Autodesk Fusion 360 part; units mm, degrees
(part 4 of 7)
extrude "Knee mount fastening and lightening (1)" cut sketch "Knee mount fastening and lightening" along normal blind 3 bodies 14 in component "05 | Femur horn link"
ref_plane "WorkPlane4" through (0, 4, 0) normal (0, 1, 0) x (0, 0, 1) in component "05 | Femur horn link"
sketch "Tibia swing clearance" plane through (0, 4, 0) normal (0, 1, 0) x (1, 0, 0) in component "05 | Femur horn link"
  line L0 (26.5, 20) -> (40, 20)
  line L1 (40, 20) -> (40, -20)
  line L2 (40, -20) -> (26.5, -20)
  line L3 (26.5, -20) -> (26.5, 20)
extrude "Tibia swing clearance (1)" cut sketch "Tibia swing clearance" along normal blind 3 bodies 14 in component "05 | Femur horn link"
ref_plane "WorkPlane1" through (0, 25, 0) normal (0, 1, 0) x (0, 0, 1) in component "06 | Knee servo mount"
sketch "Knee frame" plane through (0, 25, 0) normal (0, 1, 0) x (1, 0, 0) in component "06 | Knee servo mount"
  line L0 (19, 13.5) -> (56, 13.5)
  line L1 (56, 13.5) -> (56, -13.5)
  line L2 (56, -13.5) -> (19, -13.5)
  line L3 (19, -13.5) -> (19, 13.5)
extrude "Knee frame (1)" add sketch "Knee frame" along normal blind 3 separate body makes body 15 in component "06 | Knee servo mount"
ref_plane "WorkPlane2" through (0, 25, 0) normal (0, 1, 0) x (0, 0, 1) in component "06 | Knee servo mount"
sketch "MG90S knee body clearance" plane through (0, 25, 0) normal (0, 1, 0) x (1, 0, 0) in component "06 | Knee servo mount"
  line L0 (25.7, 6.5) -> (49.1, 6.5)
  line L1 (49.1, 6.5) -> (49.1, -6.5)
  line L2 (49.1, -6.5) -> (25.7, -6.5)
  line L3 (25.7, -6.5) -> (25.7, 6.5)
extrude "MG90S knee body clearance (1)" cut sketch "MG90S knee body clearance" along normal blind 3 bodies 15 in component "06 | Knee servo mount"
ref_plane "WorkPlane3" through (0, 25, 0) normal (0, 1, 0) x (0, 0, 1) in component "06 | Knee servo mount"
sketch "Knee ear mounting adjustment" plane through (0, 25, 0) normal (0, 1, 0) x (1, 0, 0) in component "06 | Knee servo mount"
  line L0 (24.6, 1.2) -> (24.9106, 1.1591)
  line L1 (24.9106, 1.1591) -> (25.2, 1.0392)
  line L2 (25.2, 1.0392) -> (25.4485, 0.8485)
  line L3 (25.4485, 0.8485) -> (25.6392, 0.6)
  line L4 (25.6392, 0.6) -> (25.7591, 0.3106)
  line L5 (25.7591, 0.3106) -> (25.8, 0)
  line L6 (25.8, 0) -> (25.7591, -0.3106)
  line L7 (25.7591, -0.3106) -> (25.6392, -0.6)
  line L8 (25.6392, -0.6) -> (25.4485, -0.8485)
  line L9 (25.4485, -0.8485) -> (25.2, -1.0392)
  line L10 (25.2, -1.0392) -> (24.9106, -1.1591)
  line L11 (24.9106, -1.1591) -> (24.6, -1.2)
  line L12 (24.6, -1.2) -> (22.4, -1.2)
  line L13 (22.4, -1.2) -> (22.0894, -1.1591)
  line L14 (22.0894, -1.1591) -> (21.8, -1.0392)
  line L15 (21.8, -1.0392) -> (21.5515, -0.8485)
  line L16 (21.5515, -0.8485) -> (21.3608, -0.6)
  line L17 (21.3608, -0.6) -> (21.2409, -0.3106)
  line L18 (21.2409, -0.3106) -> (21.2, 0)
  line L19 (21.2, 0) -> (21.2409, 0.3106)
  line L20 (21.2409, 0.3106) -> (21.3608, 0.6)
  line L21 (21.3608, 0.6) -> (21.5515, 0.8485)
  line L22 (21.5515, 0.8485) -> (21.8, 1.0392)
  line L23 (21.8, 1.0392) -> (22.0894, 1.1591)
  line L24 (22.0894, 1.1591) -> (22.4, 1.2)
  line L25 (22.4, 1.2) -> (24.6, 1.2)
  line L26 (52.4, 1.2) -> (52.7106, 1.1591)
  line L27 (52.7106, 1.1591) -> (53, 1.0392)
  line L28 (53, 1.0392) -> (53.2485, 0.8485)
  line L29 (53.2485, 0.8485) -> (53.4392, 0.6)
  line L30 (53.4392, 0.6) -> (53.5591, 0.3106)
  line L31 (53.5591, 0.3106) -> (53.6, 0)
  line L32 (53.6, 0) -> (53.5591, -0.3106)
  line L33 (53.5591, -0.3106) -> (53.4392, -0.6)
  line L34 (53.4392, -0.6) -> (53.2485, -0.8485)
  line L35 (53.2485, -0.8485) -> (53, -1.0392)
  line L36 (53, -1.0392) -> (52.7106, -1.1591)
  line L37 (52.7106, -1.1591) -> (52.4, -1.2)
  line L38 (52.4, -1.2) -> (50.2, -1.2)
  line L39 (50.2, -1.2) -> (49.8894, -1.1591)
  line L40 (49.8894, -1.1591) -> (49.6, -1.0392)
  line L41 (49.6, -1.0392) -> (49.3515, -0.8485)
  line L42 (49.3515, -0.8485) -> (49.1608, -0.6)
  line L43 (49.1608, -0.6) -> (49.0409, -0.3106)
  line L44 (49.0409, -0.3106) -> (49, 0)
  line L45 (49, 0) -> (49.0409, 0.3106)
  line L46 (49.0409, 0.3106) -> (49.1608, 0.6)
  line L47 (49.1608, 0.6) -> (49.3515, 0.8485)
  line L48 (49.3515, 0.8485) -> (49.6, 1.0392)
  line L49 (49.6, 1.0392) -> (49.8894, 1.1591)
  line L50 (49.8894, 1.1591) -> (50.2, 1.2)
  line L51 (50.2, 1.2) -> (52.4, 1.2)
extrude "Knee ear mounting adjustment (1)" cut sketch "Knee ear mounting adjustment" along normal blind 3 bodies 15 in component "06 | Knee servo mount"
ref_plane "WorkPlane4" through (0, 7, 0) normal (0, 1, 0) x (0, 0, 1) in component "06 | Knee servo mount"
sketch "Printed alignment tower" plane through (0, 7, 0) normal (0, 1, 0) x (1, 0, 0) in component "06 | Knee servo mount"
  circle A0 centre (22.5, 10) radius 3
extrude "Printed alignment tower (1)" add sketch "Printed alignment tower" along normal blind 18 bodies 15 in component "06 | Knee servo mount"
ref_plane "WorkPlane5" through (0, 7, 0) normal (0, 1, 0) x (0, 0, 1) in component "06 | Knee servo mount"
sketch "M2 femur through fastener" plane through (0, 7, 0) normal (0, 1, 0) x (1, 0, 0) in component "06 | Knee servo mount"
  circle A0 centre (22.5, 10) radius 1.2
extrude "M2 femur through fastener (1)" cut sketch "M2 femur through fastener" along normal blind 21 bodies 15 in component "06 | Knee servo mount"
ref_plane "WorkPlane6" through (0, 7, 0) normal (0, 1, 0) x (0, 0, 1) in component "06 | Knee servo mount"
sketch "Printed alignment tower (1)" plane through (0, 7, 0) normal (0, 1, 0) x (1, 0, 0) in component "06 | Knee servo mount"
  circle A0 centre (22.5, -10) radius 3
extrude "Printed alignment tower (2)" add sketch "Printed alignment tower (1)" along normal blind 18 bodies 15 in component "06 | Knee servo mount"
ref_plane "WorkPlane7" through (0, 7, 0) normal (0, 1, 0) x (0, 0, 1) in component "06 | Knee servo mount"
sketch "M2 femur through fastener (1)" plane through (0, 7, 0) normal (0, 1, 0) x (1, 0, 0) in component "06 | Knee servo mount"
  circle A0 centre (22.5, -10) radius 1.2
extrude "M2 femur through fastener (2)" cut sketch "M2 femur through fastener (1)" along normal blind 21 bodies 15 in component "06 | Knee servo mount"
ref_plane "WorkPlane1" through (0, 12, 0) normal (0, 1, 0) x (0, 0, 1) in component "07 | Tibia · tapered foot"
sketch "Horn hub" plane through (0, 12, 0) normal (0, 1, 0) x (1, 0, 0) in component "07 | Tibia · tapered foot"
  circle A0 centre (0, 0) radius 13.5
extrude "Horn hub (1)" add sketch "Horn hub" along normal blind 3 separate body makes body 16 in component "07 | Tibia · tapered foot"
ref_plane "WorkPlane2" through (0, 12, 0) normal (0, 1, 0) x (0, 0, 1) in component "07 | Tibia · tapered foot"
sketch "Tapered tibia blade" plane through (0, 12, 0) normal (0, 1, 0) x (1, 0, 0) in component "07 | Tibia · tapered foot"
  line L0 (4, 8) -> (72, 4)
  line L1 (72, 4) -> (80, 2.5)
  line L2 (80, 2.5) -> (80, -2.5)
  line L3 (80, -2.5) -> (72, -4)
  line L4 (72, -4) -> (4, -8)
  line L5 (4, -8) -> (4, 8)
extrude "Tapered tibia blade (1)" add sketch "Tapered tibia blade" along normal blind 3 bodies 16 in component "07 | Tibia · tapered foot"
ref_plane "WorkPlane3" through (0, 12, 0) normal (0, 1, 0) x (0, 0, 1) in component "07 | Tibia · tapered foot"
sketch "Rounded foot contact" plane through (0, 12, 0) normal (0, 1, 0) x (1, 0, 0) in component "07 | Tibia · tapered foot"
  circle A0 centre (78, 0) radius 4.5
extrude "Rounded foot contact (1)" add sketch "Rounded foot contact" along normal blind 3 bodies 16 in component "07 | Tibia · tapered foot"
ref_plane "WorkPlane4" through (0, 12, 0) normal (0, 1, 0) x (0, 0, 1) in component "07 | Tibia · tapered foot"
sketch "Stock horn screw access and adjustable M2 slots (3)" plane through (0, 12, 0) normal (0, 1, 0) x (1, 0, 0) in component "07 | Tibia · tapered foot"
  circle A0 centre (0, 0) radius 2.6
  line L0 (10.7, 1.2) -> (11.0106, 1.1591)
  line L1 (11.0106, 1.1591) -> (11.3, 1.0392)
  line L2 (11.3, 1.0392) -> (11.5485, 0.8485)
  line L3 (11.5485, 0.8485) -> (11.7392, 0.6)
  line L4 (11.7392, 0.6) -> (11.8591, 0.3106)
  line L5 (11.8591, 0.3106) -> (11.9, 0)
  line L6 (11.9, 0) -> (11.8591, -0.3106)
  line L7 (11.8591, -0.3106) -> (11.7392, -0.6)
  line L8 (11.7392, -0.6) -> (11.5485, -0.8485)
  line L9 (11.5485, -0.8485) -> (11.3, -1.0392)
  line L10 (11.3, -1.0392) -> (11.0106, -1.1591)
  line L11 (11.0106, -1.1591) -> (10.7, -1.2)
  line L12 (10.7, -1.2) -> (6.8, -1.2)
  line L13 (6.8, -1.2) -> (6.4894, -1.1591)
  line L14 (6.4894, -1.1591) -> (6.2, -1.0392)
  line L15 (6.2, -1.0392) -> (5.9515, -0.8485)
  line L16 (5.9515, -0.8485) -> (5.7608, -0.6)
  line L17 (5.7608, -0.6) -> (5.6409, -0.3106)
  line L18 (5.6409, -0.3106) -> (5.6, 0)
  line L19 (5.6, 0) -> (5.6409, 0.3106)
  line L20 (5.6409, 0.3106) -> (5.7608, 0.6)
  line L21 (5.7608, 0.6) -> (5.9515, 0.8485)
  line L22 (5.9515, 0.8485) -> (6.2, 1.0392)
  line L23 (6.2, 1.0392) -> (6.4894, 1.1591)
  line L24 (6.4894, 1.1591) -> (6.8, 1.2)
  line L25 (6.8, 1.2) -> (10.7, 1.2)
  line L26 (-6.8, 1.2) -> (-6.4894, 1.1591)
  line L27 (-6.4894, 1.1591) -> (-6.2, 1.0392)
  line L28 (-6.2, 1.0392) -> (-5.9515, 0.8485)
  line L29 (-5.9515, 0.8485) -> (-5.7608, 0.6)
  line L30 (-5.7608, 0.6) -> (-5.6409, 0.3106)
  line L31 (-5.6409, 0.3106) -> (-5.6, 0)
  line L32 (-5.6, 0) -> (-5.6409, -0.3106)
  line L33 (-5.6409, -0.3106) -> (-5.7608, -0.6)
  line L34 (-5.7608, -0.6) -> (-5.9515, -0.8485)
  line L35 (-5.9515, -0.8485) -> (-6.2, -1.0392)
  line L36 (-6.2, -1.0392) -> (-6.4894, -1.1591)
  line L37 (-6.4894, -1.1591) -> (-6.8, -1.2)
  line L38 (-6.8, -1.2) -> (-10.7, -1.2)
  line L39 (-10.7, -1.2) -> (-11.0106, -1.1591)
  line L40 (-11.0106, -1.1591) -> (-11.3, -1.0392)
  line L41 (-11.3, -1.0392) -> (-11.5485, -0.8485)
  line L42 (-11.5485, -0.8485) -> (-11.7392, -0.6)
  line L43 (-11.7392, -0.6) -> (-11.8591, -0.3106)
  line L44 (-11.8591, -0.3106) -> (-11.9, 0)
  line L45 (-11.9, 0) -> (-11.8591, 0.3106)
  line L46 (-11.8591, 0.3106) -> (-11.7392, 0.6)
  line L47 (-11.7392, 0.6) -> (-11.5485, 0.8485)
  line L48 (-11.5485, 0.8485) -> (-11.3, 1.0392)
  line L49 (-11.3, 1.0392) -> (-11.0106, 1.1591)
  line L50 (-11.0106, 1.1591) -> (-10.7, 1.2)
  line L51 (-10.7, 1.2) -> (-6.8, 1.2)
extrude "Stock horn screw access and adjustable M2 slots (1)''" cut sketch "Stock horn screw access and adjustable M2 slots (3)" along normal blind 3 bodies 16 in component "07 | Tibia · tapered foot"
ref_plane "WorkPlane5" through (0, 12, 0) normal (0, 1, 0) x (0, 0, 1) in component "07 | Tibia · tapered foot"
sketch "Lightening and optional rubber pad screw" plane through (0, 12, 0) normal (0, 1, 0) x (1, 0, 0) in component "07 | Tibia · tapered foot"
  line L0 (62, 2.3) -> (62.5953, 2.2216)
  line L1 (62.5953, 2.2216) -> (63.15, 1.9919)
  line L2 (63.15, 1.9919) -> (63.6263, 1.6263)
  line L3 (63.6263, 1.6263) -> (63.9919, 1.15)
  line L4 (63.9919, 1.15) -> (64.2216, 0.5953)
  line L5 (64.2216, 0.5953) -> (64.3, 0)
  line L6 (64.3, 0) -> (64.2216, -0.5953)
  line L7 (64.2216, -0.5953) -> (63.9919, -1.15)
  line L8 (63.9919, -1.15) -> (63.6263, -1.6263)
  line L9 (63.6263, -1.6263) -> (63.15, -1.9919)
  line L10 (63.15, -1.9919) -> (62.5953, -2.2216)
  line L11 (62.5953, -2.2216) -> (62, -2.3)
  line L12 (62, -2.3) -> (19, -2.3)
  line L13 (19, -2.3) -> (18.4047, -2.2216)
  line L14 (18.4047, -2.2216) -> (17.85, -1.9919)
  line L15 (17.85, -1.9919) -> (17.3737, -1.6263)
  line L16 (17.3737, -1.6263) -> (17.0081, -1.15)
  line L17 (17.0081, -1.15) -> (16.7784, -0.5953)
  line L18 (16.7784, -0.5953) -> (16.7, 0)
  line L19 (16.7, 0) -> (16.7784, 0.5953)
  line L20 (16.7784, 0.5953) -> (17.0081, 1.15)
  line L21 (17.0081, 1.15) -> (17.3737, 1.6263)
  line L22 (17.3737, 1.6263) -> (17.85, 1.9919)
  line L23 (17.85, 1.9919) -> (18.4047, 2.2216)
  line L24 (18.4047, 2.2216) -> (19, 2.3)
  line L25 (19, 2.3) -> (62, 2.3)
  circle A0 centre (75, 0) radius 1.7
extrude "Lightening and optional rubber pad screw (1)" cut sketch "Lightening and optional rubber pad screw" along normal blind 3 bodies 16 in component "07 | Tibia · tapered foot"
ref_plane "WorkPlane1" through (0, 0, -25) normal (0, 0, 1) x (1, 0, 0) in component "MG90S | case envelope · measure actual ears"
sketch "MG90S case nominal envelope" plane through (0, 0, -25) normal (0, 0, 1) x (1, 0, 0) in component "MG90S | case envelope · measure actual ears"
  line L0 (-16, -6.2) -> (6.8, -6.2)
  line L1 (6.8, -6.2) -> (6.8, 6.2)
  line L2 (6.8, 6.2) -> (-16, 6.2)
  line L3 (-16, 6.2) -> (-16, -6.2)
extrude "MG90S case nominal envelope (1)" add sketch "MG90S case nominal envelope" along normal blind 23.5 separate body makes body 17 in component "MG90S | case envelope · measure actual ears"
ref_plane "WorkPlane2" through (0, 0, -6) normal (0, 0, 1) x (1, 0, 0) in component "MG90S | case envelope · measure actual ears"
sketch "Mounting ears approximate" plane through (0, 0, -6) normal (0, 0, 1) x (1, 0, 0) in component "MG90S | case envelope · measure actual ears"
  line L0 (-21, -6.2) -> (11.8, -6.2)
  line L1 (11.8, -6.2) -> (11.8, 6.2)
  line L2 (11.8, 6.2) -> (-21, 6.2)
  line L3 (-21, 6.2) -> (-21, -6.2)
extrude "Mounting ears approximate (1)" add sketch "Mounting ears approximate" along normal blind 3 bodies 17 in component "MG90S | case envelope · measure actual ears"
ref_plane "WorkPlane3" through (0, 0, -6) normal (0, 0, 1) x (1, 0, 0) in component "MG90S | case envelope · measure actual ears"
sketch "Nominal ear holes" plane through (0, 0, -6) normal (0, 0, 1) x (1, 0, 0) in component "MG90S | case envelope · measure actual ears"
  circle A0 centre (-18.5, 0) radius 1
  circle A1 centre (9.3, 0) radius 1
extrude "Nominal ear holes (1)" cut sketch "Nominal ear holes" along normal blind 3 bodies 17 in component "MG90S | case envelope · measure actual ears"
ref_plane "WorkPlane4" through (0, 0, -1.5) normal (0, 0, 1) x (1, 0, 0) in component "MG90S | case envelope · measure actual ears"
sketch "Gearbox boss envelope" plane through (0, 0, -1.5) normal (0, 0, 1) x (1, 0, 0) in component "MG90S | case envelope · measure actual ears"
  circle A0 centre (0, 0) radius 5.5
extrude "Gearbox boss envelope (1)" add sketch "Gearbox boss envelope" along normal blind 2 bodies 17 in component "MG90S | case envelope · measure actual ears"
ref_plane "WorkPlane5" through (0, 0, 0.5) normal (0, 0, 1) x (1, 0, 0) in component "MG90S | case envelope · measure actual ears"
sketch "Output shaft envelope" plane through (0, 0, 0.5) normal (0, 0, 1) x (1, 0, 0) in component "MG90S | case envelope · measure actual ears"
  circle A0 centre (0, 0) radius 2.3
extrude "Output shaft envelope (1)" add sketch "Output shaft envelope" along normal blind 1.5 bodies 17 in component "MG90S | case envelope · measure actual ears"
ref_plane "WorkPlane1" through (0, 0, 2) normal (0, 0, 1) x (1, 0, 0) in component "Stock double horn | reference only"
sketch "Supplied horn approximate" plane through (0, 0, 2) normal (0, 0, 1) x (1, 0, 0) in component "Stock double horn | reference only"
  line L0 (10.5, -2.5) -> (11.147, -2.4148)
  line L1 (11.147, -2.4148) -> (11.75, -2.1651)
  line L2 (11.75, -2.1651) -> (12.2678, -1.7678)
  line L3 (12.2678, -1.7678) -> (12.6651, -1.25)
  line L4 (12.6651, -1.25) -> (12.9148, -0.647)
  line L5 (12.9148, -0.647) -> (13, 0)
  line L6 (13, 0) -> (12.9148, 0.647)
  line L7 (12.9148, 0.647) -> (12.6651, 1.25)
  line L8 (12.6651, 1.25) -> (12.2678, 1.7678)
  line L9 (12.2678, 1.7678) -> (11.75, 2.1651)
  line L10 (11.75, 2.1651) -> (11.147, 2.4148)
  line L11 (11.147, 2.4148) -> (10.5, 2.5)
  line L12 (10.5, 2.5) -> (-10.5, 2.5)
  line L13 (-10.5, 2.5) -> (-11.147, 2.4148)
  line L14 (-11.147, 2.4148) -> (-11.75, 2.1651)
  line L15 (-11.75, 2.1651) -> (-12.2678, 1.7678)
  line L16 (-12.2678, 1.7678) -> (-12.6651, 1.25)
  line L17 (-12.6651, 1.25) -> (-12.9148, 0.647)
  line L18 (-12.9148, 0.647) -> (-13, 0)
  line L19 (-13, 0) -> (-12.9148, -0.647)
  line L20 (-12.9148, -0.647) -> (-12.6651, -1.25)
  line L21 (-12.6651, -1.25) -> (-12.2678, -1.7678)
  line L22 (-12.2678, -1.7678) -> (-11.75, -2.1651)
  line L23 (-11.75, -2.1651) -> (-11.147, -2.4148)
  line L24 (-11.147, -2.4148) -> (-10.5, -2.5)
  line L25 (-10.5, -2.5) -> (10.5, -2.5)
extrude "Supplied horn approximate (1)" add sketch "Supplied horn approximate" along normal blind 2 separate body makes body 18 in component "Stock double horn | reference only"
ref_plane "WorkPlane2" through (0, 0, 0.5) normal (0, 0, 1) x (1, 0, 0) in component "Stock double horn | reference only"
sketch "Horn hub (2)" plane through (0, 0, 0.5) normal (0, 0, 1) x (1, 0, 0) in component "Stock double horn | reference only"
  circle A0 centre (0, 0) radius 5.5
extrude "Horn hub (1)'" add sketch "Horn hub (2)" along normal blind 3.5 bodies 18 in component "Stock double horn | reference only"
ref_plane "WorkPlane3" through (0, 0, 0.5) normal (0, 0, 1) x (1, 0, 0) in component "Stock double horn | reference only"
sketch "Stock horn screw references" plane through (0, 0, 0.5) normal (0, 0, 1) x (1, 0, 0) in component "Stock double horn | reference only"
  circle A0 centre (0, 0) radius 2.35
  circle A1 centre (-8.5, 0) radius 0.8
  circle A2 centre (8.5, 0) radius 0.8
extrude "Stock horn screw references (1)" cut sketch "Stock horn screw references" along normal blind 3.5 bodies 18 in component "Stock double horn | reference only"
sketch "Servo fit coupon" plane through (0, 0, 0) normal (0, 0, 1) x (1, 0, 0) in component "FIT TEST ONLY · servo and horn coupon"
  line L0 (-24, -11) -> (15, -11)
  line L1 (15, -11) -> (15, 11)
  line L2 (15, 11) -> (-24, 11)
  line L3 (-24, 11) -> (-24, -11)
extrude "Servo fit coupon (1)" add sketch "Servo fit coupon" along normal blind 3 separate body makes body 19 in component "FIT TEST ONLY · servo and horn coupon"
sketch "Servo test opening and slots" plane through (0, 0, 0) normal (0, 0, 1) x (1, 0, 0) in component "FIT TEST ONLY · servo and horn coupon"
  line L0 (-16.3, -6.5) -> (7.1, -6.5)
  line L1 (7.1, -6.5) -> (7.1, 6.5)
  line L2 (7.1, 6.5) -> (-16.3, 6.5)
  line L3 (-16.3, 6.5) -> (-16.3, -6.5)
  line L4 (-17.4, -1.2) -> (-17.0894, -1.1591)
  line L5 (-17.0894, -1.1591) -> (-16.8, -1.0392)
  line L6 (-16.8, -1.0392) -> (-16.5515, -0.8485)
  line L7 (-16.5515, -0.8485) -> (-16.3608, -0.6)
  line L8 (-16.3608, -0.6) -> (-16.2409, -0.3106)
  line L9 (-16.2409, -0.3106) -> (-16.2, 0)
  line L10 (-16.2, 0) -> (-16.2409, 0.3106)
  line L11 (-16.2409, 0.3106) -> (-16.3608, 0.6)
  line L12 (-16.3608, 0.6) -> (-16.5515, 0.8485)
  line L13 (-16.5515, 0.8485) -> (-16.8, 1.0392)
  line L14 (-16.8, 1.0392) -> (-17.0894, 1.1591)
  line L15 (-17.0894, 1.1591) -> (-17.4, 1.2)
  line L16 (-17.4, 1.2) -> (-19.6, 1.2)
  line L17 (-19.6, 1.2) -> (-19.9106, 1.1591)
  line L18 (-19.9106, 1.1591) -> (-20.2, 1.0392)
  line L19 (-20.2, 1.0392) -> (-20.4485, 0.8485)
  line L20 (-20.4485, 0.8485) -> (-20.6392, 0.6)
  line L21 (-20.6392, 0.6) -> (-20.7591, 0.3106)
  line L22 (-20.7591, 0.3106) -> (-20.8, 0)
  line L23 (-20.8, 0) -> (-20.7591, -0.3106)
  line L24 (-20.7591, -0.3106) -> (-20.6392, -0.6)
  line L25 (-20.6392, -0.6) -> (-20.4485, -0.8485)
  line L26 (-20.4485, -0.8485) -> (-20.2, -1.0392)
  line L27 (-20.2, -1.0392) -> (-19.9106, -1.1591)
  line L28 (-19.9106, -1.1591) -> (-19.6, -1.2)
  line L29 (-19.6, -1.2) -> (-17.4, -1.2)
  line L30 (10.4, -1.2) -> (10.7106, -1.1591)
  line L31 (10.7106, -1.1591) -> (11, -1.0392)
  line L32 (11, -1.0392) -> (11.2485, -0.8485)
  line L33 (11.2485, -0.8485) -> (11.4392, -0.6)
  line L34 (11.4392, -0.6) -> (11.5591, -0.3106)
  line L35 (11.5591, -0.3106) -> (11.6, 0)
  line L36 (11.6, 0) -> (11.5591, 0.3106)
  line L37 (11.5591, 0.3106) -> (11.4392, 0.6)
  line L38 (11.4392, 0.6) -> (11.2485, 0.8485)
  line L39 (11.2485, 0.8485) -> (11, 1.0392)
  line L40 (11, 1.0392) -> (10.7106, 1.1591)
  line L41 (10.7106, 1.1591) -> (10.4, 1.2)
  line L42 (10.4, 1.2) -> (8.2, 1.2)
  line L43 (8.2, 1.2) -> (7.8894, 1.1591)
  line L44 (7.8894, 1.1591) -> (7.6, 1.0392)
  line L45 (7.6, 1.0392) -> (7.3515, 0.8485)
  line L46 (7.3515, 0.8485) -> (7.1608, 0.6)
  line L47 (7.1608, 0.6) -> (7.0409, 0.3106)
  line L48 (7.0409, 0.3106) -> (7, 0)
  line L49 (7, 0) -> (7.0409, -0.3106)
  line L50 (7.0409, -0.3106) -> (7.1608, -0.6)
  line L51 (7.1608, -0.6) -> (7.3515, -0.8485)
  line L52 (7.3515, -0.8485) -> (7.6, -1.0392)
  line L53 (7.6, -1.0392) -> (7.8894, -1.1591)
  line L54 (7.8894, -1.1591) -> (8.2, -1.2)
  line L55 (8.2, -1.2) -> (10.4, -1.2)
extrude "Servo test opening and slots (1)" cut sketch "Servo test opening and slots" along normal blind 3 bodies 19 in component "FIT TEST ONLY · servo and horn coupon"
sketch "Connected horn test hub" plane through (0, 0, 0) normal (0, 0, 1) x (1, 0, 0) in component "FIT TEST ONLY · servo and horn coupon"
  line L0 (32, -13.5) -> (35.4941, -13.04)
  line L1 (35.4941, -13.04) -> (38.75, -11.6913)
  line L2 (38.75, -11.6913) -> (41.5459, -9.5459)
  line L3 (41.5459, -9.5459) -> (43.6913, -6.75)
  line L4 (43.6913, -6.75) -> (45.04, -3.4941)
  line L5 (45.04, -3.4941) -> (45.5, 0)
  line L6 (45.5, 0) -> (45.04, 3.4941)
  line L7 (45.04, 3.4941) -> (43.6913, 6.75)
  line L8 (43.6913, 6.75) -> (41.5459, 9.5459)
  line L9 (41.5459, 9.5459) -> (38.75, 11.6913)
  line L10 (38.75, 11.6913) -> (35.4941, 13.04)
  line L11 (35.4941, 13.04) -> (32, 13.5)
  line L12 (32, 13.5) -> (26, 13.5)
  line L13 (26, 13.5) -> (22.5059, 13.04)
  line L14 (22.5059, 13.04) -> (19.25, 11.6913)
  line L15 (19.25, 11.6913) -> (16.4541, 9.5459)
  line L16 (16.4541, 9.5459) -> (14.3087, 6.75)
  line L17 (14.3087, 6.75) -> (12.96, 3.4941)
  line L18 (12.96, 3.4941) -> (12.5, 0)
  line L19 (12.5, 0) -> (12.96, -3.4941)
  line L20 (12.96, -3.4941) -> (14.3087, -6.75)
  line L21 (14.3087, -6.75) -> (16.4541, -9.5459)
  line L22 (16.4541, -9.5459) -> (19.25, -11.6913)
  line L23 (19.25, -11.6913) -> (22.5059, -13.04)
  line L24 (22.5059, -13.04) -> (26, -13.5)
  line L25 (26, -13.5) -> (32, -13.5)
extrude "Connected horn test hub (1)" add sketch "Connected horn test hub" along normal blind 3 bodies 19 in component "FIT TEST ONLY · servo and horn coupon"
sketch "Stock horn screw access and adjustable M2 slots (4)" plane through (0, 0, 0) normal (0, 0, 1) x (1, 0, 0) in component "FIT TEST ONLY · servo and horn coupon"
  circle A0 centre (30, 0) radius 2.6
  line L0 (40.7, -1.2) -> (41.0106, -1.1591)
  line L1 (41.0106, -1.1591) -> (41.3, -1.0392)
  line L2 (41.3, -1.0392) -> (41.5485, -0.8485)
  line L3 (41.5485, -0.8485) -> (41.7392, -0.6)
  line L4 (41.7392, -0.6) -> (41.8591, -0.3106)
  line L5 (41.8591, -0.3106) -> (41.9, 0)
  line L6 (41.9, 0) -> (41.8591, 0.3106)
  line L7 (41.8591, 0.3106) -> (41.7392, 0.6)
  line L8 (41.7392, 0.6) -> (41.5485, 0.8485)
  line L9 (41.5485, 0.8485) -> (41.3, 1.0392)
  line L10 (41.3, 1.0392) -> (41.0106, 1.1591)
  line L11 (41.0106, 1.1591) -> (40.7, 1.2)
  line L12 (40.7, 1.2) -> (36.8, 1.2)
  line L13 (36.8, 1.2) -> (36.4894, 1.1591)
  line L14 (36.4894, 1.1591) -> (36.2, 1.0392)
  line L15 (36.2, 1.0392) -> (35.9515, 0.8485)
  line L16 (35.9515, 0.8485) -> (35.7608, 0.6)
  line L17 (35.7608, 0.6) -> (35.6409, 0.3106)
  line L18 (35.6409, 0.3106) -> (35.6, 0)
  line L19 (35.6, 0) -> (35.6409, -0.3106)
  line L20 (35.6409, -0.3106) -> (35.7608, -0.6)
  line L21 (35.7608, -0.6) -> (35.9515, -0.8485)
  line L22 (35.9515, -0.8485) -> (36.2, -1.0392)
  line L23 (36.2, -1.0392) -> (36.4894, -1.1591)
  line L24 (36.4894, -1.1591) -> (36.8, -1.2)
  line L25 (36.8, -1.2) -> (40.7, -1.2)
  line L26 (23.2, -1.2) -> (23.5106, -1.1591)
  line L27 (23.5106, -1.1591) -> (23.8, -1.0392)
  line L28 (23.8, -1.0392) -> (24.0485, -0.8485)
  line L29 (24.0485, -0.8485) -> (24.2392, -0.6)
  line L30 (24.2392, -0.6) -> (24.3591, -0.3106)
  line L31 (24.3591, -0.3106) -> (24.4, 0)
  line L32 (24.4, 0) -> (24.3591, 0.3106)
  line L33 (24.3591, 0.3106) -> (24.2392, 0.6)
  line L34 (24.2392, 0.6) -> (24.0485, 0.8485)
  line L35 (24.0485, 0.8485) -> (23.8, 1.0392)
  line L36 (23.8, 1.0392) -> (23.5106, 1.1591)
  line L37 (23.5106, 1.1591) -> (23.2, 1.2)
  line L38 (23.2, 1.2) -> (19.3, 1.2)
  line L39 (19.3, 1.2) -> (18.9894, 1.1591)
  line L40 (18.9894, 1.1591) -> (18.7, 1.0392)
  line L41 (18.7, 1.0392) -> (18.4515, 0.8485)
  line L42 (18.4515, 0.8485) -> (18.2608, 0.6)
  line L43 (18.2608, 0.6) -> (18.1409, 0.3106)
  line L44 (18.1409, 0.3106) -> (18.1, 0)
  line L45 (18.1, 0) -> (18.1409, -0.3106)
  line L46 (18.1409, -0.3106) -> (18.2608, -0.6)
  line L47 (18.2608, -0.6) -> (18.4515, -0.8485)
  line L48 (18.4515, -0.8485) -> (18.7, -1.0392)
  line L49 (18.7, -1.0392) -> (18.9894, -1.1591)
  line L50 (18.9894, -1.1591) -> (19.3, -1.2)
  line L51 (19.3, -1.2) -> (23.2, -1.2)
extrude "Stock horn screw access and adjustable M2 slots (1)'''" cut sketch "Stock horn screw access and adjustable M2 slots (4)" along normal blind 3 bodies 19 in component "FIT TEST ONLY · servo and horn coupon"
sketch "Sketch2" plane through (0, 0, 0) normal (0, 0, 1) x (1, 0, 0)
  point P0 (49, 0)
  point P1 (59, 0)
  point P2 (49, 10)
ref_plane "WorkPlane1" through (49, 0, 0) normal (0, 0, 1) x (1, 0, 0)
sketch "Sketch3" plane through (0, 0, 0) normal (0, 0, 1) x (1, 0, 0)
  circle A0 centre (49, 0) radius 1
sketch "Sketch4" plane through (0, 0, 0) normal (0, 0, 1) x (1, 0, 0)
  point P0 (79, 0)
  point P1 (79, 0)
  point P2 (89, 0)
ref_plane "WorkPlane2" through (79, 0, 38) normal (0, 1, 0) x (-1, 0, 0)
sketch "Sketch5" plane through (0, 0, 0) normal (0, 1, 0) x (1, 0, 0)
  circle A0 centre (79, -38) radius 1
sketch "Sketch6" plane through (0, 0, 0) normal (0, 0, 1) x (1, 0, 0)
  point P0 (117.0649, 0)
  point P1 (117.0649, 0)
  point P2 (127.0649, 0)
ref_plane "WorkPlane3" through (117.0649, 0, 20.25) normal (0, 1, 0) x (-1, 0, 0)
sketch "Sketch7" plane through (0, 0, 0) normal (0, 1, 0) x (1, 0, 0)
  circle A0 centre (117.0649, -20.25) radius 1
sketch "Sketch8" plane through (0, 0, 0) normal (0, 0, 1) x (1, 0, 0)
  point P0 (24.5, 42.4352)
  point P1 (34.5, 42.4352)
  point P2 (24.5, 52.4352)
ref_plane "WorkPlane4" through (24.5, 42.4352, 0) normal (0, 0, 1) x (1, 0, 0)
sketch "Sketch9" plane through (0, 0, 0) normal (0, 0, 1) x (1, 0, 0)
  circle A0 centre (24.5, 42.4352) radius 1
sketch "Sketch10" plane through (0, 0, 0) normal (0, 0, 1) x (1, 0, 0)
  point P0 (39.5, 68.416)
  point P1 (39.5, 68.416)
  point P2 (44.5, 77.0763)
ref_plane "WorkPlane5" through (39.5, 68.416, 38) normal (-0.866025, 0.5, 0) x (-0.5, -0.866025, 0)
sketch "Sketch11" plane through (0, 0, 0) normal (-0.866025, 0.5, 0) x (-0.5, -0.866025, 0)
  circle A0 centre (-79, 38) radius 1
sketch "Sketch12" plane through (0, 0, 0) normal (0, 0, 1) x (1, 0, 0)
  point P0 (58.5325, 101.3812)
  point P1 (58.5325, 101.3812)
  point P2 (63.5325, 110.0415)
ref_plane "WorkPlane6" through (58.5325, 101.3812, 20.25) normal (-0.866025, 0.5, 0) x (-0.5, -0.866025, 0)
sketch "Sketch13" plane through (0, 0, 0) normal (-0.866025, 0.5, 0) x (-0.5, -0.866025, 0)
  circle A0 centre (-117.0649, 20.25) radius 1
sketch "Sketch14" plane through (0, 0, 0) normal (0, 0, 1) x (1, 0, 0)
  point P0 (-24.5, 42.4352)
  point P1 (-14.5, 42.4352)
  point P2 (-24.5, 52.4352)
ref_plane "WorkPlane7" through (-24.5, 42.4352, 0) normal (0, 0, 1) x (1, 0, 0)
sketch "Sketch15" plane through (0, 0, 0) normal (0, 0, 1) x (1, 0, 0)
  circle A0 centre (-24.5, 42.4352) radius 1
sketch "Sketch16" plane through (0, 0, 0) normal (0, 0, 1) x (1, 0, 0)
  point P0 (-39.5, 68.416)
  point P1 (-39.5, 68.416)
  point P2 (-44.5, 77.0763)
ref_plane "WorkPlane8" through (-39.5, 68.416, 38) normal (-0.866025, -0.5, 0) x (0.5, -0.866025, 0)
sketch "Sketch17" plane through (0, 0, 0) normal (-0.866025, -0.5, 0) x (0.5, -0.866025, 0)
  circle A0 centre (-79, 38) radius 1
sketch "Sketch18" plane through (0, 0, 0) normal (0, 0, 1) x (1, 0, 0)
  point P0 (-58.5325, 101.3812)
  point P1 (-58.5325, 101.3812)
  point P2 (-63.5325, 110.0415)
ref_plane "WorkPlane9" through (-58.5325, 101.3812, 20.25) normal (-0.866025, -0.5, 0) x (0.5, -0.866025, 0)
sketch "Sketch19" plane through (0, 0, 0) normal (-0.866025, -0.5, 0) x (0.5, -0.866025, 0)
  circle A0 centre (-117.0649, 20.25) radius 1
sketch "Sketch20" plane through (0, 0, 0) normal (0, 0, 1) x (1, 0, 0)
  point P0 (-49, 0)
  point P1 (-39, 0)
  point P2 (-49, 10)
ref_plane "WorkPlane10" through (-49, 0, 0) normal (0, 0, 1) x (1, 0, 0)
sketch "Sketch21" plane through (0, 0, 0) normal (0, 0, 1) x (1, 0, 0)
  circle A0 centre (-49, 0) radius 1
sketch "Sketch22" plane through (0, 0, 0) normal (0, 0, 1) x (1, 0, 0)
  point P0 (-79, 0)
  point P1 (-79, 0)
  point P2 (-89, 0)
ref_plane "WorkPlane11" through (-79, 0, 38) normal (0, -1, 0) x (1, 0, 0)
sketch "Sketch23" plane through (0, 0, 0) normal (0, -1, 0) x (-1, 0, 0)
  circle A0 centre (79, -38) radius 1
sketch "Sketch24" plane through (0, 0, 0) normal (0, 0, 1) x (1, 0, 0)
  point P0 (-117.0649, 0)
  point P1 (-117.0649, 0)
  point P2 (-127.0649, 0)
ref_plane "WorkPlane12" through (-117.0649, 0, 20.25) normal (0, -1, 0) x (1, 0, 0)
sketch "Sketch25" plane through (0, 0, 0) normal (0, -1, 0) x (-1, 0, 0)
  circle A0 centre (117.0649, -20.25) radius 1
sketch "Sketch26" plane through (0, 0, 0) normal (0, 0, 1) x (1, 0, 0)
  point P0 (-24.5, -42.4352)
  point P1 (-14.5, -42.4352)
  point P2 (-24.5, -32.4352)
ref_plane "WorkPlane13" through (-24.5, -42.4352, 0) normal (0, 0, 1) x (1, 0, 0)
sketch "Sketch27" plane through (0, 0, 0) normal (0, 0, 1) x (1, 0, 0)
  circle A0 centre (-24.5, -42.4352) radius 1
sketch "Sketch28" plane through (0, 0, 0) normal (0, 0, 1) x (1, 0, 0)
  point P0 (-39.5, -68.416)
  point P1 (-39.5, -68.416)
  point P2 (-44.5, -77.0763)
ref_plane "WorkPlane14" through (-39.5, -68.416, 38) normal (0.866025, -0.5, 0) x (0.5, 0.866025, 0)
sketch "Sketch29" plane through (0, 0, 0) normal (0.866025, -0.5, 0) x (0.5, 0.866025, 0)
  circle A0 centre (-79, 38) radius 1
sketch "Sketch30" plane through (0, 0, 0) normal (0, 0, 1) x (1, 0, 0)
  point P0 (-58.5325, -101.3812)
  point P1 (-58.5325, -101.3812)
  point P2 (-63.5325, -110.0415)
ref_plane "WorkPlane15" through (-58.5325, -101.3812, 20.25) normal (0.866025, -0.5, 0) x (0.5, 0.866025, 0)
sketch "Sketch31" plane through (0, 0, 0) normal (0.866025, -0.5, 0) x (0.5, 0.866025, 0)
  circle A0 centre (-117.0649, 20.25) radius 1
sketch "Sketch32" plane through (0, 0, 0) normal (0, 0, 1) x (1, 0, 0)
  point P0 (24.5, -42.4352)
  point P1 (34.5, -42.4352)
  point P2 (24.5, -32.4352)
ref_plane "WorkPlane16" through (24.5, -42.4352, 0) normal (0, 0, 1) x (1, 0, 0)
sketch "Sketch33" plane through (0, 0, 0) normal (0, 0, 1) x (1, 0, 0)
  circle A0 centre (24.5, -42.4352) radius 1
sketch "Sketch34" plane through (0, 0, 0) normal (0, 0, 1) x (1, 0, 0)
  point P0 (39.5, -68.416)
  point P1 (39.5, -68.416)
  point P2 (44.5, -77.0763)
ref_plane "WorkPlane17" through (39.5, -68.416, 38) normal (0.866025, 0.5, 0) x (-0.5, 0.866025, 0)
sketch "Sketch35" plane through (0, 0, 0) normal (0.866025, 0.5, 0) x (-0.5, 0.866025, 0)
  circle A0 centre (-79, 38) radius 1
sketch "Sketch36" plane through (0, 0, 0) normal (0, 0, 1) x (1, 0, 0)
  point P0 (58.5325, -101.3812)
  point P1 (58.5325, -101.3812)
  point P2 (63.5325, -110.0415)
ref_plane "WorkPlane18" through (58.5325, -101.3812, 20.25) normal (0.866025, 0.5, 0) x (-0.5, 0.866025, 0)
sketch "Sketch37" plane through (0, 0, 0) normal (0.866025, 0.5, 0) x (-0.5, 0.866025, 0)
  circle A0 centre (-117.0649, 20.25) radius 1
ref_plane "WorkPlane1" through (0, 0, -9) normal (0, 0, 1) x (1, 0, 0) in component "HARDWARE | M2x8 servo ears · unthreaded reference"
sketch "Bolt shank" plane through (0, 0, -9) normal (0, 0, 1) x (1, 0, 0) in component "HARDWARE | M2x8 servo ears · unthreaded reference"
  circle A0 centre (-18.5, 0) radius 1
extrude "Bolt shank (1)" add sketch "Bolt shank" along normal blind 8 separate body makes body 20 in component "HARDWARE | M2x8 servo ears · unthreaded reference"
ref_plane "WorkPlane2" through (0, 0, -11) normal (0, 0, 1) x (1, 0, 0) in component "HARDWARE | M2x8 servo ears · unthreaded reference"
sketch "Socket head envelope" plane through (0, 0, -11) normal (0, 0, 1) x (1, 0, 0) in component "HARDWARE | M2x8 servo ears · unthreaded reference"
  circle A0 centre (-18.5, 0) radius 1.9
extrude "Socket head envelope (1)" add sketch "Socket head envelope" along normal blind 2 bodies 20 in component "HARDWARE | M2x8 servo ears · unthreaded reference"
ref_plane "WorkPlane3" through (0, 0, -3) normal (0, 0, 1) x (1, 0, 0) in component "HARDWARE | M2x8 servo ears · unthreaded reference"
sketch "Washer" plane through (0, 0, -3) normal (0, 0, 1) x (1, 0, 0) in component "HARDWARE | M2x8 servo ears · unthreaded reference"
  circle A0 centre (-18.5, 0) radius 2
extrude "Washer (1)" add sketch "Washer" along normal blind 0.4 separate body makes body 21 in component "HARDWARE | M2x8 servo ears · unthreaded reference"
ref_plane "WorkPlane4" through (0, 0, -3) normal (0, 0, 1) x (1, 0, 0) in component "HARDWARE | M2x8 servo ears · unthreaded reference"
sketch "Washer clearance" plane through (0, 0, -3) normal (0, 0, 1) x (1, 0, 0) in component "HARDWARE | M2x8 servo ears · unthreaded reference"
  circle A0 centre (-18.5, 0) radius 1.2
extrude "Washer clearance (1)" cut sketch "Washer clearance" along normal blind 0.4 bodies 21 in component "HARDWARE | M2x8 servo ears · unthreaded reference"
ref_plane "WorkPlane5" through (0, 0, -2.6) normal (0, 0, 1) x (1, 0, 0) in component "HARDWARE | M2x8 servo ears · unthreaded reference"
sketch "Hex nut" plane through (0, 0, -2.6) normal (0, 0, 1) x (1, 0, 0) in component "HARDWARE | M2x8 servo ears · unthreaded reference"
  line L0 (-16.1906, 0) -> (-17.3453, 2)
  line L1 (-17.3453, 2) -> (-19.6547, 2)
  line L2 (-19.6547, 2) -> (-20.8094, 0)
  line L3 (-20.8094, 0) -> (-19.6547, -2)
  line L4 (-19.6547, -2) -> (-17.3453, -2)
  line L5 (-17.3453, -2) -> (-16.1906, 0)
extrude "Hex nut (1)" add sketch "Hex nut" along normal blind 1.6 separate body makes body 22 in component "HARDWARE | M2x8 servo ears · unthreaded reference"
ref_plane "WorkPlane6" through (0, 0, -2.6) normal (0, 0, 1) x (1, 0, 0) in component "HARDWARE | M2x8 servo ears · unthreaded reference"
sketch "Nut thread envelope clearance" plane through (0, 0, -2.6) normal (0, 0, 1) x (1, 0, 0) in component "HARDWARE | M2x8 servo ears · unthreaded reference"
  circle A0 centre (-18.5, 0) radius 1.15
extrude "Nut thread envelope clearance (1)" cut sketch "Nut thread envelope clearance" along normal blind 1.6 bodies 22 in component "HARDWARE | M2x8 servo ears · unthreaded reference"
ref_plane "WorkPlane7" through (0, 0, -9) normal (0, 0, 1) x (1, 0, 0) in component "HARDWARE | M2x8 servo ears · unthreaded reference"
sketch "Bolt shank (1)" plane through (0, 0, -9) normal (0, 0, 1) x (1, 0, 0) in component "HARDWARE | M2x8 servo ears · unthreaded reference"
  circle A0 centre (9.3, 0) radius 1
extrude "Bolt shank (2)" add sketch "Bolt shank (1)" along normal blind 8 separate body makes body 23 in component "HARDWARE | M2x8 servo ears · unthreaded reference"
ref_plane "WorkPlane8" through (0, 0, -11) normal (0, 0, 1) x (1, 0, 0) in component "HARDWARE | M2x8 servo ears · unthreaded reference"
sketch "Socket head envelope (1)" plane through (0, 0, -11) normal (0, 0, 1) x (1, 0, 0) in component "HARDWARE | M2x8 servo ears · unthreaded reference"
  circle A0 centre (9.3, 0) radius 1.9
extrude "Socket head envelope (2)" add sketch "Socket head envelope (1)" along normal blind 2 bodies 23 in component "HARDWARE | M2x8 servo ears · unthreaded reference"
ref_plane "WorkPlane9" through (0, 0, -3) normal (0, 0, 1) x (1, 0, 0) in component "HARDWARE | M2x8 servo ears · unthreaded reference"
sketch "Washer (1)" plane through (0, 0, -3) normal (0, 0, 1) x (1, 0, 0) in component "HARDWARE | M2x8 servo ears · unthreaded reference"
  circle A0 centre (9.3, 0) radius 2
extrude "Washer (2)" add sketch "Washer (1)" along normal blind 0.4 separate body makes body 24 in component "HARDWARE | M2x8 servo ears · unthreaded reference"
ref_plane "WorkPlane10" through (0, 0, -3) normal (0, 0, 1) x (1, 0, 0) in component "HARDWARE | M2x8 servo ears · unthreaded reference"
sketch "Washer clearance (1)" plane through (0, 0, -3) normal (0, 0, 1) x (1, 0, 0) in component "HARDWARE | M2x8 servo ears · unthreaded reference"
  circle A0 centre (9.3, 0) radius 1.2
extrude "Washer clearance (2)" cut sketch "Washer clearance (1)" along normal blind 0.4 bodies 24 in component "HARDWARE | M2x8 servo ears · unthreaded reference"
ref_plane "WorkPlane11" through (0, 0, -2.6) normal (0, 0, 1) x (1, 0, 0) in component "HARDWARE | M2x8 servo ears · unthreaded reference"
sketch "Hex nut (1)" plane through (0, 0, -2.6) normal (0, 0, 1) x (1, 0, 0) in component "HARDWARE | M2x8 servo ears · unthreaded reference"
  line L0 (11.6094, 0) -> (10.4547, 2)
  line L1 (10.4547, 2) -> (8.1453, 2)
  line L2 (8.1453, 2) -> (6.9906, 0)
  line L3 (6.9906, 0) -> (8.1453, -2)
  line L4 (8.1453, -2) -> (10.4547, -2)
  line L5 (10.4547, -2) -> (11.6094, 0)
extrude "Hex nut (2)" add sketch "Hex nut (1)" along normal blind 1.6 separate body makes body 25 in component "HARDWARE | M2x8 servo ears · unthreaded reference"
ref_plane "WorkPlane12" through (0, 0, -2.6) normal (0, 0, 1) x (1, 0, 0) in component "HARDWARE | M2x8 servo ears · unthreaded reference"
sketch "Nut thread envelope clearance (1)" plane through (0, 0, -2.6) normal (0, 0, 1) x (1, 0, 0) in component "HARDWARE | M2x8 servo ears · unthreaded reference"
  circle A0 centre (9.3, 0) radius 1.15
extrude "Nut thread envelope clearance (2)" cut sketch "Nut thread envelope clearance (1)" along normal blind 1.6 bodies 25 in component "HARDWARE | M2x8 servo ears · unthreaded reference"
ref_plane "WorkPlane1" through (0, 0, 2) normal (0, 0, 1) x (1, 0, 0) in component "HARDWARE | M1_6x8 stock horn · unthreaded reference"
sketch "Bolt shank (2)" plane through (0, 0, 2) normal (0, 0, 1) x (1, 0, 0) in component "HARDWARE | M1_6x8 stock horn · unthreaded reference"
  circle A0 centre (-8.5, 0) radius 0.8
extrude "Bolt shank (1)'" add sketch "Bolt shank (2)" along normal blind 8 separate body makes body 26 in component "HARDWARE | M1_6x8 stock horn · unthreaded reference"
ref_plane "WorkPlane2" through (0, 0, 0.4) normal (0, 0, 1) x (1, 0, 0) in component "HARDWARE | M1_6x8 stock horn · unthreaded reference"
sketch "Socket head envelope (2)" plane through (0, 0, 0.4) normal (0, 0, 1) x (1, 0, 0) in component "HARDWARE | M1_6x8 stock horn · unthreaded reference"
  circle A0 centre (-8.5, 0) radius 1.5
extrude "Socket head envelope (1)'" add sketch "Socket head envelope (2)" along normal blind 1.6 bodies 26 in component "HARDWARE | M1_6x8 stock horn · unthreaded reference"
ref_plane "WorkPlane3" through (0, 0, 7) normal (0, 0, 1) x (1, 0, 0) in component "HARDWARE | M1_6x8 stock horn · unthreaded reference"
sketch "Washer (2)" plane through (0, 0, 7) normal (0, 0, 1) x (1, 0, 0) in component "HARDWARE | M1_6x8 stock horn · unthreaded reference"
  circle A0 centre (-8.5, 0) radius 1.6
extrude "Washer (1)'" add sketch "Washer (2)" along normal blind 0.4 separate body makes body 27 in component "HARDWARE | M1_6x8 stock horn · unthreaded reference"
ref_plane "WorkPlane4" through (0, 0, 7) normal (0, 0, 1) x (1, 0, 0) in component "HARDWARE | M1_6x8 stock horn · unthreaded reference"
sketch "Washer clearance (2)" plane through (0, 0, 7) normal (0, 0, 1) x (1, 0, 0) in component "HARDWARE | M1_6x8 stock horn · unthreaded reference"
  circle A0 centre (-8.5, 0) radius 1
extrude "Washer clearance (1)'" cut sketch "Washer clearance (2)" along normal blind 0.4 bodies 27 in component "HARDWARE | M1_6x8 stock horn · unthreaded reference"
ref_plane "WorkPlane5" through (0, 0, 7.4) normal (0, 0, 1) x (1, 0, 0) in component "HARDWARE | M1_6x8 stock horn · unthreaded reference"
sketch "Hex nut (2)" plane through (0, 0, 7.4) normal (0, 0, 1) x (1, 0, 0) in component "HARDWARE | M1_6x8 stock horn · unthreaded reference"
  line L0 (-6.6525, 0) -> (-7.5762, 1.6)
  line L1 (-7.5762, 1.6) -> (-9.4238, 1.6)
  line L2 (-9.4238, 1.6) -> (-10.3475, 0)
  line L3 (-10.3475, 0) -> (-9.4238, -1.6)
  line L4 (-9.4238, -1.6) -> (-7.5762, -1.6)
  line L5 (-7.5762, -1.6) -> (-6.6525, 0)
extrude "Hex nut (1)'" add sketch "Hex nut (2)" along normal blind 1.3 separate body makes body 28 in component "HARDWARE | M1_6x8 stock horn · unthreaded reference"
ref_plane "WorkPlane6" through (0, 0, 7.4) normal (0, 0, 1) x (1, 0, 0) in component "HARDWARE | M1_6x8 stock horn · unthreaded reference"
sketch "Nut thread envelope clearance (2)" plane through (0, 0, 7.4) normal (0, 0, 1) x (1, 0, 0) in component "HARDWARE | M1_6x8 stock horn · unthreaded reference"
  circle A0 centre (-8.5, 0) radius 0.95
extrude "Nut thread envelope clearance (1)'" cut sketch "Nut thread envelope clearance (2)" along normal blind 1.3 bodies 28 in component "HARDWARE | M1_6x8 stock horn · unthreaded reference"
ref_plane "WorkPlane7" through (0, 0, 2) normal (0, 0, 1) x (1, 0, 0) in component "HARDWARE | M1_6x8 stock horn · unthreaded reference"
sketch "Bolt shank (1) (2)" plane through (0, 0, 2) normal (0, 0, 1) x (1, 0, 0) in component "HARDWARE | M1_6x8 stock horn · unthreaded reference"
  circle A0 centre (8.5, 0) radius 0.8
extrude "Bolt shank (2)'" add sketch "Bolt shank (1) (2)" along normal blind 8 separate body makes body 29 in component "HARDWARE | M1_6x8 stock horn · unthreaded reference"
ref_plane "WorkPlane8" through (0, 0, 0.4) normal (0, 0, 1) x (1, 0, 0) in component "HARDWARE | M1_6x8 stock horn · unthreaded reference"
sketch "Socket head envelope (1) (2)" plane through (0, 0, 0.4) normal (0, 0, 1) x (1, 0, 0) in component "HARDWARE | M1_6x8 stock horn · unthreaded reference"
  circle A0 centre (8.5, 0) radius 1.5
extrude "Socket head envelope (2)'" add sketch "Socket head envelope (1) (2)" along normal blind 1.6 bodies 29 in component "HARDWARE | M1_6x8 stock horn · unthreaded reference"
ref_plane "WorkPlane9" through (0, 0, 7) normal (0, 0, 1) x (1, 0, 0) in component "HARDWARE | M1_6x8 stock horn · unthreaded reference"
sketch "Washer (1) (2)" plane through (0, 0, 7) normal (0, 0, 1) x (1, 0, 0) in component "HARDWARE | M1_6x8 stock horn · unthreaded reference"
  circle A0 centre (8.5, 0) radius 1.6
extrude "Washer (2)'" add sketch "Washer (1) (2)" along normal blind 0.4 separate body makes body 30 in component "HARDWARE | M1_6x8 stock horn · unthreaded reference"
ref_plane "WorkPlane10" through (0, 0, 7) normal (0, 0, 1) x (1, 0, 0) in component "HARDWARE | M1_6x8 stock horn · unthreaded reference"
sketch "Washer clearance (1) (2)" plane through (0, 0, 7) normal (0, 0, 1) x (1, 0, 0) in component "HARDWARE | M1_6x8 stock horn · unthreaded reference"
  circle A0 centre (8.5, 0) radius 1
extrude "Washer clearance (2)'" cut sketch "Washer clearance (1) (2)" along normal blind 0.4 bodies 30 in component "HARDWARE | M1_6x8 stock horn · unthreaded reference"
ref_plane "WorkPlane11" through (0, 0, 7.4) normal (0, 0, 1) x (1, 0, 0) in component "HARDWARE | M1_6x8 stock horn · unthreaded reference"
sketch "Hex nut (1) (2)" plane through (0, 0, 7.4) normal (0, 0, 1) x (1, 0, 0) in component "HARDWARE | M1_6x8 stock horn · unthreaded reference"
  line L0 (10.3475, 0) -> (9.4238, 1.6)
  line L1 (9.4238, 1.6) -> (7.5762, 1.6)
  line L2 (7.5762, 1.6) -> (6.6525, 0)
  line L3 (6.6525, 0) -> (7.5762, -1.6)
  line L4 (7.5762, -1.6) -> (9.4238, -1.6)
  line L5 (9.4238, -1.6) -> (10.3475, 0)
extrude "Hex nut (2)'" add sketch "Hex nut (1) (2)" along normal blind 1.3 separate body makes body 31 in component "HARDWARE | M1_6x8 stock horn · unthreaded reference"
ref_plane "WorkPlane12" through (0, 0, 7.4) normal (0, 0, 1) x (1, 0, 0) in component "HARDWARE | M1_6x8 stock horn · unthreaded reference"
sketch "Nut thread envelope clearance (1) (2)" plane through (0, 0, 7.4) normal (0, 0, 1) x (1, 0, 0) in component "HARDWARE | M1_6x8 stock horn · unthreaded reference"
  circle A0 centre (8.5, 0) radius 0.95
extrude "Nut thread envelope clearance (2)'" cut sketch "Nut thread envelope clearance (1) (2)" along normal blind 1.3 bodies 31 in component "HARDWARE | M1_6x8 stock horn · unthreaded reference"
sketch "Countersunk M3 shank" plane through (0, 0, 0) normal (0, 0, 1) x (1, 0, 0) in component "HARDWARE | M3x10 countersunk hip · reference"
  circle A0 centre (17, 4) radius 1.5
extrude "Countersunk M3 shank (1)" add sketch "Countersunk M3 shank" along normal blind 8.5 separate body makes body 32 in component "HARDWARE | M3x10 countersunk hip · reference"
ref_plane "WorkPlane1" through (0, 0, 8.5) normal (0, 0, 1) x (1, 0, 0) in component "HARDWARE | M3x10 countersunk hip · reference"
sketch "Flush 90 degree screw head section" plane through (0, 0, 8.5) normal (0, 0, 1) x (1, 0, 0) in component "HARDWARE | M3x10 countersunk hip · reference"
  circle A0 centre (17, 4) radius 1.5
ref_plane "WorkPlane2" through (0, 0, 10) normal (0, 0, 1) x (1, 0, 0) in component "HARDWARE | M3x10 countersunk hip · reference"
sketch "Flush 90 degree screw head section (1)" plane through (0, 0, 10) normal (0, 0, 1) x (1, 0, 0) in component "HARDWARE | M3x10 countersunk hip · reference"
  circle A0 centre (17, 4) radius 3
loft "Flush 90 degree screw head" add profiles "Flush 90 degree screw head section", "Flush 90 degree screw head section (1)" section 1 section 2 bodies 32 in component "HARDWARE | M3x10 countersunk hip · reference"
ref_plane "WorkPlane3" through (0, 0, 3.6) normal (0, 0, 1) x (1, 0, 0) in component "HARDWARE | M3x10 countersunk hip · reference"
sketch "M3 underside washer" plane through (0, 0, 3.6) normal (0, 0, 1) x (1, 0, 0) in component "HARDWARE | M3x10 countersunk hip · reference"
  circle A0 centre (17, 4) radius 2.75
extrude "M3 underside washer (1)" add sketch "M3 underside washer" along normal blind 0.4 separate body makes body 33 in component "HARDWARE | M3x10 countersunk hip · reference"
ref_plane "WorkPlane4" through (0, 0, 3.6) normal (0, 0, 1) x (1, 0, 0) in component "HARDWARE | M3x10 countersunk hip · reference"
sketch "Washer clearance (3)" plane through (0, 0, 3.6) normal (0, 0, 1) x (1, 0, 0) in component "HARDWARE | M3x10 countersunk hip · reference"
  circle A0 centre (17, 4) radius 1.7
extrude "Washer clearance (1)''" cut sketch "Washer clearance (3)" along normal blind 0.4 bodies 33 in component "HARDWARE | M3x10 countersunk hip · reference"
ref_plane "WorkPlane5" through (0, 0, 1.2) normal (0, 0, 1) x (1, 0, 0) in component "HARDWARE | M3x10 countersunk hip · reference"
sketch "M3 underside nut" plane through (0, 0, 1.2) normal (0, 0, 1) x (1, 0, 0) in component "HARDWARE | M3x10 countersunk hip · reference"
  line L0 (20.1754, 4) -> (18.5877, 6.75)
  line L1 (18.5877, 6.75) -> (15.4123, 6.75)
  line L2 (15.4123, 6.75) -> (13.8246, 4)
  line L3 (13.8246, 4) -> (15.4123, 1.25)
  line L4 (15.4123, 1.25) -> (18.5877, 1.25)
  line L5 (18.5877, 1.25) -> (20.1754, 4)
extrude "M3 underside nut (1)" add sketch "M3 underside nut" along normal blind 2.4 separate body makes body 34 in component "HARDWARE | M3x10 countersunk hip · reference"
ref_plane "WorkPlane6" through (0, 0, 1.2) normal (0, 0, 1) x (1, 0, 0) in component "HARDWARE | M3x10 countersunk hip · reference"
sketch "Nut thread envelope clearance (3)" plane through (0, 0, 1.2) normal (0, 0, 1) x (1, 0, 0) in component "HARDWARE | M3x10 countersunk hip · reference"
  circle A0 centre (17, 4) radius 1.65
extrude "Nut thread envelope clearance (1)''" cut sketch "Nut thread envelope clearance (3)" along normal blind 2.4 bodies 34 in component "HARDWARE | M3x10 countersunk hip · reference"
sketch "Countersunk M3 shank (1)" plane through (0, 0, 0) normal (0, 0, 1) x (1, 0, 0) in component "HARDWARE | M3x10 countersunk hip · reference"
  circle A0 centre (42, 4) radius 1.5
extrude "Countersunk M3 shank (2)" add sketch "Countersunk M3 shank (1)" along normal blind 8.5 separate body makes body 35 in component "HARDWARE | M3x10 countersunk hip · reference"
ref_plane "WorkPlane7" through (0, 0, 8.5) normal (0, 0, 1) x (1, 0, 0) in component "HARDWARE | M3x10 countersunk hip · reference"
sketch "Flush 90 degree screw head section (2)" plane through (0, 0, 8.5) normal (0, 0, 1) x (1, 0, 0) in component "HARDWARE | M3x10 countersunk hip · reference"
  circle A0 centre (42, 4) radius 1.5
ref_plane "WorkPlane8" through (0, 0, 10) normal (0, 0, 1) x (1, 0, 0) in component "HARDWARE | M3x10 countersunk hip · reference"
sketch "Flush 90 degree screw head section (3)" plane through (0, 0, 10) normal (0, 0, 1) x (1, 0, 0) in component "HARDWARE | M3x10 countersunk hip · reference"
  circle A0 centre (42, 4) radius 3
loft "Flush 90 degree screw head (1)" add profiles "Flush 90 degree screw head section (2)", "Flush 90 degree screw head section (3)" section 1 section 2 bodies 35 in component "HARDWARE | M3x10 countersunk hip · reference"
ref_plane "WorkPlane9" through (0, 0, 3.6) normal (0, 0, 1) x (1, 0, 0) in component "HARDWARE | M3x10 countersunk hip · reference"
sketch "M3 underside washer (1)" plane through (0, 0, 3.6) normal (0, 0, 1) x (1, 0, 0) in component "HARDWARE | M3x10 countersunk hip · reference"
  circle A0 centre (42, 4) radius 2.75
extrude "M3 underside washer (2)" add sketch "M3 underside washer (1)" along normal blind 0.4 separate body makes body 36 in component "HARDWARE | M3x10 countersunk hip · reference"
ref_plane "WorkPlane10" through (0, 0, 3.6) normal (0, 0, 1) x (1, 0, 0) in component "HARDWARE | M3x10 countersunk hip · reference"
sketch "Washer clearance (1) (3)" plane through (0, 0, 3.6) normal (0, 0, 1) x (1, 0, 0) in component "HARDWARE | M3x10 countersunk hip · reference"
  circle A0 centre (42, 4) radius 1.7